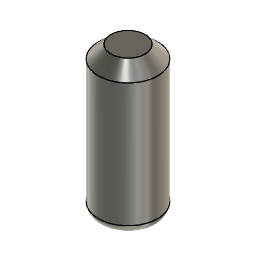
Padlock (Autodesk Fusion 360 archive; units mm, degrees)
design "Key pin 6"
Autodesk Fusion 360 part; units mm, degrees
sketch "Sketch1" plane through (0, 0, 0) normal (0, 0, 1) x (1, 0, 0)
  circle A0 centre (100, 0) radius 2.35
  dimension "d1" = 4.7
  measures "d1" diameter of A0
extrude "Extrude1" add sketch "Sketch1" along normal blind 11.5
fillet "Fillet1" radius 0.7 1 edges at (97.809, -0.8498, 0)
chamfer "Chamfer1" distance 1 angle 45 1 edges at (97.809, -0.8498, 11.5) tangent chain off

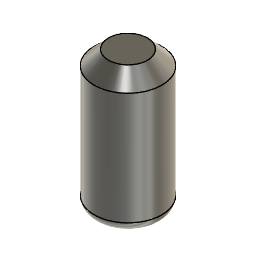
design "Key pin 4"
Autodesk Fusion 360 part; units mm, degrees
sketch "Sketch1" plane through (0, 0, 0) normal (0, 0, 1) x (1, 0, 0)
  circle A0 centre (80, 0) radius 2.35
  dimension "d1" = 4.7
  measures "d1" diameter of A0
extrude "Extrude1" add sketch "Sketch1" along normal blind 9.5
fillet "Fillet1" radius 0.7 1 edges at (77.809, -0.8498, 0)
chamfer "Chamfer1" distance 1 angle 45 1 edges at (77.809, -0.8498, 9.5) tangent chain off

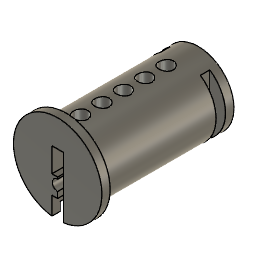
design "Plug"
Autodesk Fusion 360 part; units mm, degrees
sketch "Sketch1" plane through (0, 0, 0) normal (0, 1, 0) x (1, 0, 0)
  circle A0 centre (0, 0) radius 12.5
  line L0 (-2, -6) -> (2, -6)
  line L1 (2, -6) -> (2, 12.339)
  line L2 (-2, -6) -> (-2, 12.339)
  line L3 (0, 2.5) -> (0, 9)
  line L4 (0, 9) -> (-2, 9)
  circle A1 centre (0, 5) radius 1.8828
  circle A2 centre (0, 0) radius 15.5
  line L5 (2, 12.339) -> (2, 15.3704)
  line L6 (-2, 12.339) -> (-2, 15.3704)
  line L7 (0, 2.5) -> (-2, 2.5)
  line L8 (-2, 0) -> (-2, 2.5)
  dimension "d1" = 25
  dimension "d4" = 3
  constraint coincident A0.centre A2.centre
  constraint horizontal L0
  constraint coincident A0 L1.end
  constraint perpendicular L0 L1
  constraint coincident A0 L2.end
  constraint perpendicular L0 L2
  constraint coincident L2 L8.start
  constraint coincident L2 L4.end
  constraint perpendicular L2 L4
  constraint coincident L3 A1.centre
  constraint coincident A2 L5.end
  constraint parallel L1 L5
  constraint coincident A2 L6.end
  constraint parallel L2 L6
  constraint coincident L2 L7.end
  constraint perpendicular L2 L7
  measures "d1" diameter of A0
extrude "Extrude2" add sketch "Sketch1" along normal blind 40 contours A0 L0 L1 L2 L8 | L2 L3 L4 A1 L7
extrude "Extrude3" add sketch "Sketch1" against normal blind 3 contours A0 L0 L1 L2 L8 | A0 A2 L5 L6 | L2 L3 L4 A1 L7 picked at (-2.7474, 14.2058)
ref_plane "WorkPlane1" through (0, 26.0944, 12.5) normal (0, 0, 1) x (-1, 0, 0)
sketch "Sketch2" plane through (0, 0, 12.5) normal (0, 0, 1) x (1, 0, 0)
  line L0 (0, 0) -> (0, 2.5)
  circle A0 centre (0, 5) radius 2.5
  circle A1 centre (0, 12.5) radius 2.5
  line L1 (0, 7.5) -> (0, 10)
  circle A2 centre (0, 20) radius 2.5
  line L2 (0, 15) -> (0, 17.5)
  circle A3 centre (0, 27.5) radius 2.5
  line L3 (0, 22.5) -> (0, 25)
  circle A4 centre (0, 35) radius 2.5
  line L4 (0, 30) -> (0, 32.5)
  line L5 (0, 37.5) -> (0, 40)
  dimension "d11" = 2.5
  dimension "d12" = 5
  dimension "d15" = 0
  dimension "d16" = 30
  constraint coincident L0.start origin
  constraint vertical L0
  constraint coincident L0.end A0
  constraint coincident A4 L5.start
  constraint vertical L5
  measures "d11" distance of L0.start L0.end
  measures "d12" diameter of A0
extrude "Extrude4" cut sketch "Sketch2" against normal blind 15
extrude "Extrude5" cut 1 faces at (0, 0, 14.4721) along direction (0, -1, 0) blind 0.1
sketch "Sketch3" plane through (0, 40, 0) normal (0, 1, 0) x (-1, 0, 0)
  line L0 (2, 6) -> (2, -2.5)
  line L1 (2, -2.5) -> (0, -2.5)
  line L2 (0, -2.5) -> (0, -3.1172)
  arc A0 (0, -6.8828) -> (0, -3.1172) centre (0, -5) ccw
  line L3 (0, -6.8828) -> (0, -9)
  line L4 (0, -9) -> (2, -9)
  line L5 (2, -9) -> (2, -12.339)
  arc A1 (2, -12.339) -> (-2, -12.339) centre (0, 0) ccw
  line L6 (-2, -12.339) -> (-2, 6)
  line L7 (-2, 6) -> (2, 6)
sketch "Sketch4" plane through (0, 40, 0) normal (0, 1, 0) x (-1, 0, 0)
  circle A0 centre (0, 0) radius 12.5
  line L0 (-7, 13) -> (7, 13)
  line L1 (7, 13) -> (7, -13)
  line L2 (7, -13) -> (-7, -13)
  line L3 (-7, -13) -> (-7, 13)
  line L4 (-7, 13) -> (7, -13) construction
  line L5 (7, 13) -> (-7, -13) construction
  dimension "d21" = 25
  constraint coincident A0.centre origin
  constraint horizontal L0
  constraint perpendicular L0 L1
  constraint parallel L0 L2
  constraint parallel L1 L3
  constraint coincident L4 A0.centre
  constraint coincident L5 A0.centre
  measures "d21" diameter of A0
extrude "Extrude6" add sketch "Sketch4" sketch "Sketch3" along normal blind 6.3 contours A0 L3 of sketch 2
extrude "Extrude7" cut sketch "Sketch4" along normal blind 3.3 contours A0 L1 | A0 L3

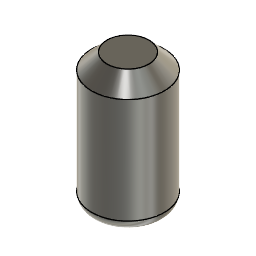
design "Key pin 3"
Autodesk Fusion 360 part; units mm, degrees
sketch "Sketch1" plane through (0, 0, 0) normal (0, 0, 1) x (1, 0, 0)
  circle A0 centre (70, 0) radius 2.35
  dimension "d1" = 4.7
  measures "d1" diameter of A0
extrude "Extrude1" add sketch "Sketch1" along normal blind 8.5
fillet "Fillet1" radius 0.7 1 edges at (67.809, -0.8498, 0)
chamfer "Chamfer1" distance 1 angle 45 1 edges at (67.809, -0.8498, 8.5) tangent chain off

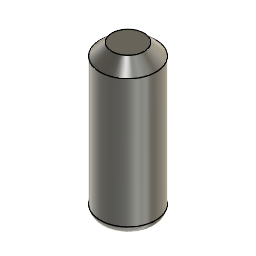
design "Key pin 7"
Autodesk Fusion 360 part; units mm, degrees
sketch "Sketch1" plane through (0, 0, 0) normal (0, 0, 1) x (1, 0, 0)
  circle A0 centre (110, 0) radius 2.35
  dimension "d1" = 4.7
  measures "d1" diameter of A0
extrude "Extrude1" add sketch "Sketch1" along normal blind 12.5
fillet "Fillet1" radius 0.7 1 edges at (107.809, -0.8498, 0)
chamfer "Chamfer1" distance 1 angle 45 1 edges at (107.809, -0.8498, 12.5) tangent chain off

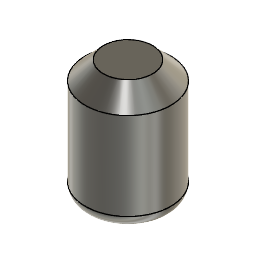
design "Key pin 1"
Autodesk Fusion 360 part; units mm, degrees
sketch "Sketch1" plane through (0, 0, 0) normal (0, 0, 1) x (1, 0, 0)
  circle A0 centre (50, 0) radius 2.35
  dimension "d1" = 4.7
  measures "d1" diameter of A0
extrude "Extrude1" add sketch "Sketch1" along normal blind 6.5
fillet "Fillet1" radius 0.7 1 edges at (47.809, -0.8498, 0)
chamfer "Chamfer1" distance 1 angle 45 1 edges at (47.809, -0.8498, 6.5) tangent chain off

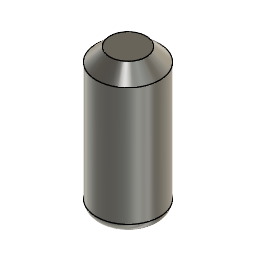
design "Key pin 5"
Autodesk Fusion 360 part; units mm, degrees
sketch "Sketch1" plane through (0, 0, 0) normal (0, 0, 1) x (1, 0, 0)
  circle A0 centre (90, 0) radius 2.35
  dimension "d1" = 4.7
  measures "d1" diameter of A0
extrude "Extrude1" add sketch "Sketch1" along normal blind 10.5
fillet "Fillet1" radius 0.7 1 edges at (87.809, -0.8498, 0)
chamfer "Chamfer1" distance 1 angle 45 1 edges at (87.809, -0.8498, 10.5) tangent chain off

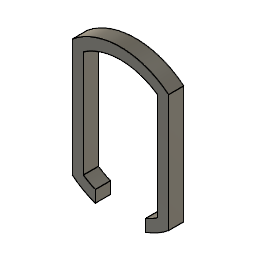
design "C-clip"
Autodesk Fusion 360 part; units mm, degrees
sketch "Sketch1" plane through (0, 0, 0) normal (0, 1, 0) x (1, 0, 0)
  line L0 (-83, 10.3562) -> (-83, -10.3562)
  line L1 (-97, -10.3562) -> (-97, 10.3562)
  line L2 (-97, 15) -> (-83, -15) construction
  line L3 (-83, 15) -> (-97, -15) construction
  arc A0 (-97, -10.3562) -> (-83, -10.3562) centre (-90, 0) ccw
  arc A1 (-83, 10.3562) -> (-97, 10.3562) centre (-90, 0) ccw
  line L4 (-82.7, 10.5143) -> (-82.7, -10.5143)
  arc A2 (-97.3, -10.5143) -> (-82.7, -10.5143) centre (-90, 0) ccw
  line L5 (-97.3, -10.5143) -> (-97.3, 10.5143)
  arc A3 (-82.7, 10.5143) -> (-97.3, 10.5143) centre (-90, 0) ccw
  line L6 (-80.5, 11.6082) -> (-80.5, -11.6082)
  arc A4 (-99.5, -11.6082) -> (-80.5, -11.6082) centre (-90, 0) ccw
  line L7 (-99.5, -11.6082) -> (-99.5, 11.6082)
  arc A5 (-80.5, 11.6082) -> (-99.5, 11.6082) centre (-90, 0) ccw
  line L8 (-94.9454, 14.1613) -> (-94.9454, 11.8061)
  line L9 (-85.0767, 14.169) -> (-85.0767, 11.8153)
  point P0 (-90, 0)
  dimension "d1" = 25
  dimension "d2" = 14
  dimension "d3" = 30
  dimension "d4" = 0.3
  dimension "d5" = 2.2
  constraint parallel L0 L1
  constraint coincident L2 P0
  constraint coincident L3 P0
  constraint coincident P0 A0.centre
  constraint concentric A0 A1
  constraint coincident A5 L8.start
  constraint coincident A3 L8.end
  constraint vertical L8
  constraint coincident A5 L9.start
  constraint coincident A3 L9.end
  constraint vertical L9
  measures "d1" diameter of A0
  measures "d2" distance of L2.end L3.end
  measures "d3" distance of L3.start L2.end
extrude "Extrude1" add sketch "Sketch1" along normal blind 3 contours L4 A2 L5 A3 L6 A4 L7 A5 L8 L9

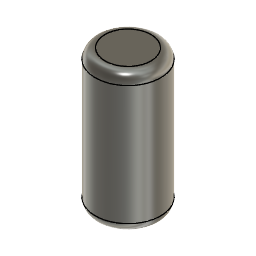
design "Driver pin"
Autodesk Fusion 360 part; units mm, degrees
sketch "Sketch1" plane through (0, 0, 0) normal (0, 0, 1) x (1, 0, 0)
  circle A0 centre (40, 0) radius 2.35
  dimension "d1" = 4.7
  measures "d1" diameter of A0
extrude "Extrude1" add sketch "Sketch1" along normal blind 10
fillet "Fillet1" radius 0.7 2 edges at (37.809, -0.8498, 10) (37.809, -0.8498, 0)

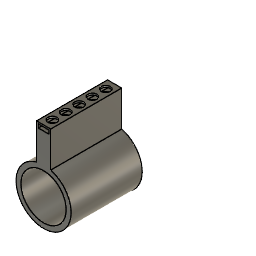
design "Bible"
Autodesk Fusion 360 part; units mm, degrees
sketch "Sketch1" plane through (0, 0, 0) normal (0, 1, 0) x (1, 0, 0)
  circle A0 centre (0, 0) radius 12.7
  circle A1 centre (0, 0) radius 15.5
  dimension "d1" = 25.4
  dimension "d2" = 31
  constraint coincident A0.centre A1.centre
  measures "d1" diameter of A0
  measures "d2" diameter of A1
extrude "Extrude1" add sketch "Sketch1" along normal blind 40
sketch "Sketch2" plane through (0, 0, 0) normal (0, -1, 0) x (1, 0, 0)
  circle A0 centre (0, 0) radius 12.7
  circle A1 centre (0, 0) radius 15.5
  line L0 (-4, 13) -> (4, 13)
  line L1 (4, 13) -> (4, 34.9748)
  line L2 (4, 34.9748) -> (-4, 34.9748)
  line L3 (-4, 34.9748) -> (-4, 13)
  constraint horizontal L0
  constraint vertical L1
  constraint horizontal L2
  constraint vertical L3
extrude "Extrude2" add sketch "Sketch2" against normal blind 40 contours A1 L1 L2 L3
sketch "Sketch3" plane through (0, 0, 34.9748) normal (0, 0, 1) x (-1, 0, 0)
  line L0 (4, 0) -> (-4, 0)
  line L1 (-4, 0) -> (-4, -40)
  line L2 (-4, -40) -> (4, -40)
  line L3 (4, -40) -> (4, 0)
  line L4 (0, 0) -> (0, -2.5)
  circle A0 centre (0, -5) radius 2.5
  line L5 (0, -7.5) -> (0, -10)
  circle A1 centre (0, -12.5) radius 2.5
  line L6 (0, -15) -> (0, -17.5)
  circle A2 centre (0, -20) radius 2.5
  line L7 (0, -22.5) -> (0, -25)
  circle A3 centre (0, -27.5) radius 2.5
  line L8 (0, -30) -> (0, -32.5)
  circle A4 centre (0, -35) radius 2.5
  line L9 (0, -37.5) -> (0, -40)
  dimension "d7" = 2.5
  dimension "d8" = 5
  dimension "d11" = 0
  dimension "d12" = -30
  constraint coincident L4.start origin
  constraint perpendicular L0 L4
  constraint coincident L4.end A0
  constraint coincident A4 L9.start
  constraint midpoint L2 L9.end
  constraint perpendicular L2 L9
  measures "d7" distance of L4.start L4.end
  measures "d8" diameter of A0
extrude "Extrude3" cut sketch "Sketch3" against normal blind 28 contours A0 | A4 | A1 | A3 | A2
sketch "Sketch4" plane through (0, 0, 0) normal (0, -1, 0) x (1, 0, 0)
  line L0 (-3, 34) -> (3, 34)
  line L1 (3, 34) -> (3, 32)
  line L2 (3, 32) -> (-3, 32)
  line L3 (-3, 32) -> (-3, 34)
  line L4 (-3, 34) -> (3, 32) construction
  line L5 (3, 34) -> (-3, 32) construction
  point P0 (0, 33)
  dimension "d15" = 6
  constraint horizontal L0
  constraint perpendicular L0 L1
  constraint parallel L0 L2
  constraint parallel L1 L3
  constraint coincident L4 P0
  constraint coincident L5 P0
  measures "d15" distance of L1.end L2.end
extrude "Extrude4" cut sketch "Sketch4" against normal blind 95

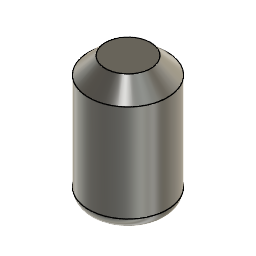
design "Key pin 2"
Autodesk Fusion 360 part; units mm, degrees
sketch "Sketch1" plane through (0, 0, 0) normal (0, 0, 1) x (1, 0, 0)
  circle A0 centre (60, 0) radius 2.35
  dimension "d1" = 4.7
  measures "d1" diameter of A0
extrude "Extrude1" add sketch "Sketch1" along normal blind 7.5
fillet "Fillet1" radius 0.7 1 edges at (57.809, -0.8498, 0)
chamfer "Chamfer1" distance 1 angle 45 1 edges at (57.809, -0.8498, 7.5) tangent chain off
